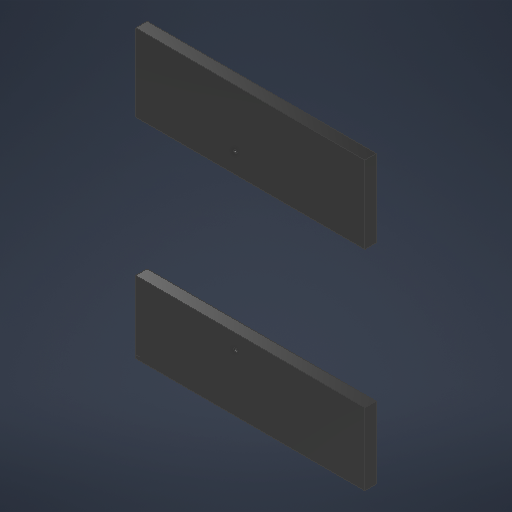
# Autodesk Inventor part: Part67
Saved by Autodesk Inventor 2027.1 (Build 311270010, 270A)
## iProperties
Created: 2026-10-12
Part Number: Part67
Material: Generic
Document SubType Name: Modeling
Designer: daniel
Density: 1 g/cm^3
Appearance: Default
Mass: 260.456 g
Surface Area: 629.456 cm^2
Volume: 260.456 cm^3
Author: daniel
Autodesk Inventor part; units mm, degrees
ref_plane "YZ Plane" through (0, 0, 0) normal (1, 0, 0) x (0, 1, 0)
ref_plane "XZ Plane" through (0, 0, 0) normal (0, 1, 0) x (-1, 0, 0)
ref_plane "XY Plane" through (0, 0, 0) normal (0, 0, 1) x (1, 0, 0)
sketch "Sketch1" plane through (0, 0, 0) normal (0, 0, 1) x (1, 0, 0)
  line L0 (100.0665, -125.0665) -> (100.0665, 124.9335)
  line L1 (100.0665, 124.9335) -> (100.0665, -125.0665)
  line L2 (-99.9335, 124.9335) -> (-99.9335, -125.0665)
  line L3 (100.0665, 37.4335) -> (100.0665, 57.4335)
  line L4 (97.0665, 57.4335) -> (97.0665, 77.3335)
  line L5 (97.0665, 77.3335) -> (100.0665, 77.3335)
  line L6 (97.0665, 77.3335) -> (100.0665, 77.3335)
  line L7 (100.0665, 77.3335) -> (100.0665, 57.4335)
  line L8 (97.0665, 97.3335) -> (97.0665, 77.3335)
  line L9 (100.0665, 121.9335) -> (100.0665, 124.9335)
  line L10 (100.0665, 57.4335) -> (97.0665, 57.4335)
  line L11 (100.0665, 57.4335) -> (97.0665, 57.4335)
  line L12 (57.0665, 121.9335) -> (37.1665, 121.9335)
  line L13 (100.0665, 77.3335) -> (100.0665, 97.3335)
  line L14 (97.0665, 57.4335) -> (97.0665, 37.4335)
  line L15 (-99.9335, -125.0665) -> (100.0665, -125.0665)
  line L16 (100.0665, 124.9335) -> (77.0665, 124.9335)
  line L17 (37.1665, 124.9335) -> (57.0665, 124.9335)
  line L18 (100.0665, 124.9335) -> (-99.9335, 124.9335)
  line L19 (77.0665, 121.9335) -> (100.0665, 121.9335)
  line L20 (77.0665, 121.9335) -> (57.0665, 121.9335)
  line L21 (77.0665, 124.9335) -> (77.0665, 121.9335)
  line L22 (77.0665, 124.9335) -> (77.0665, 121.9335)
  line L23 (37.1665, 121.9335) -> (37.1665, 124.9335)
  line L24 (37.1665, 124.9335) -> (37.1665, 121.9335)
  line L25 (37.1665, 121.9335) -> (17.1665, 121.9335)
  line L26 (17.1665, 124.9335) -> (37.1665, 124.9335)
  line L27 (57.0665, 124.9335) -> (57.0665, 121.9335)
  line L28 (57.0665, 121.9335) -> (57.0665, 124.9335)
  line L29 (-22.7335, 121.9335) -> (-22.7335, 124.9335)
  line L30 (-92.7335, 124.9335) -> (-72.7335, 124.9335)
  line L31 (-72.7335, 124.9335) -> (-99.9335, 124.9335)
  line L32 (-99.9335, 124.9335) -> (-99.9335, 121.9335)
  line L33 (-99.9335, 124.9335) -> (-96.9335, 124.9335)
  line L34 (-96.9335, 124.9335) -> (-96.9335, 97.3335)
  line L35 (-99.9335, 97.3335) -> (-99.9335, 124.9335)
  line L36 (-99.9335, 97.9335) -> (-99.9335, 121.9335)
  line L37 (-96.9335, 97.3335) -> (-99.9335, 97.3335)
  line L38 (-99.9335, 97.3335) -> (-96.9335, 97.3335)
  line L39 (-96.9335, 97.3335) -> (-96.9335, 77.3335)
  line L40 (-96.9335, 77.3335) -> (-99.9335, 77.3335)
  line L41 (-96.9335, 77.3335) -> (-99.9335, 77.3335)
  line L42 (-99.9335, 77.3335) -> (-99.9335, 97.3335)
  line L43 (-99.9335, 121.9335) -> (-96.9335, 121.9335)
  line L44 (17.1665, 121.9335) -> (17.1665, 124.9335)
  line L45 (17.1665, 121.9335) -> (-2.7335, 121.9335)
  line L46 (-2.7335, 121.9335) -> (-2.7335, 124.9335)
  line L47 (-2.7335, 124.9335) -> (17.1665, 124.9335)
  line L48 (17.1665, 124.9335) -> (17.1665, 121.9335)
  line L49 (-2.7335, 121.9335) -> (-22.7335, 121.9335)
  line L50 (-2.7335, 124.9335) -> (-2.7335, 121.9335)
  line L51 (-22.7335, 124.9335) -> (-2.7335, 124.9335)
  line L52 (-99.9335, 57.4335) -> (-96.9335, 57.4335)
  line L53 (-99.9335, 57.4335) -> (-96.9335, 57.4335)
  line L54 (-99.9335, 77.3335) -> (-99.9335, 57.4335)
  line L55 (-96.9335, 37.4335) -> (-99.9335, 37.4335)
  line L56 (-96.9335, 57.4335) -> (-96.9335, 37.4335)
  line L57 (-99.9335, 37.4335) -> (-99.9335, 57.4335)
  line L58 (-99.9335, 37.4335) -> (-96.9335, 37.4335)
  line L59 (-99.9335, 17.5335) -> (-99.9335, 37.4335)
  line L60 (-96.9335, 37.4335) -> (-96.9335, 17.5335)
  line L61 (-96.9335, 57.4335) -> (-96.9335, 77.3335)
  line L62 (-96.9335, 17.5335) -> (-99.9335, 17.5335)
  line L63 (-99.9335, 17.5335) -> (-96.9335, 17.5335)
  line L64 (-96.9335, -2.4665) -> (-99.9335, -2.4665)
  line L65 (-99.9335, -2.4665) -> (-96.9335, -2.4665)
  line L66 (-96.9335, 17.5335) -> (-96.9335, -2.4665)
  line L67 (-96.9335, -22.3665) -> (-99.9335, -22.3665)
  line L68 (-99.9335, -22.3665) -> (-96.9335, -22.3665)
  line L69 (-96.9335, -2.4665) -> (-96.9335, -22.3665)
  line L70 (-99.9335, -22.3665) -> (-99.9335, -2.4665)
  line L71 (-99.9335, -2.4665) -> (-99.9335, 17.5335)
  line L72 (-96.9335, -22.3665) -> (-96.9335, -42.3665)
  line L73 (-99.9335, -42.3665) -> (-99.9335, -22.3665)
  line L74 (-96.9335, -42.3665) -> (-99.9335, -42.3665)
  line L75 (-99.9335, -42.3665) -> (-96.9335, -42.3665)
  line L76 (-96.9335, -62.2665) -> (-99.9335, -62.2665)
  line L77 (-99.9335, -62.2665) -> (-99.9335, -42.3665)
  line L78 (-99.9335, -62.2665) -> (-96.9335, -62.2665)
  line L79 (-99.9335, -82.2665) -> (-99.9335, -62.2665)
  line L80 (-96.9335, -62.2665) -> (-96.9335, -82.2665)
  line L81 (-96.9335, -42.3665) -> (-96.9335, -62.2665)
  line L82 (-96.9335, -82.2665) -> (-99.9335, -82.2665)
  line L83 (-99.9335, -82.2665) -> (-96.9335, -82.2665)
  line L84 (-96.9335, -82.2665) -> (-96.9335, -102.1665)
  line L85 (-99.9335, -102.1665) -> (-99.9335, -82.2665)
  line L86 (-96.9335, -102.1665) -> (-99.9335, -102.1665)
  line L87 (-99.9335, -102.1665) -> (-96.9335, -102.1665)
  line L88 (-96.9335, -102.1665) -> (-96.9335, -122.1665)
  line L89 (-96.9335, -122.1665) -> (-99.9335, -122.1665)
  line L90 (-92.6335, -122.0665) -> (-99.9335, -122.0665)
  line L91 (-99.9335, -125.0665) -> (-42.6335, -125.0665)
  line L92 (-99.9335, -122.0665) -> (-99.9335, -125.0665)
  line L93 (-99.9335, -122.1665) -> (-99.9335, -102.1665)
  line L94 (97.0665, 97.3335) -> (100.0665, 97.3335)
  line L95 (100.0665, 97.3335) -> (97.0665, 97.3335)
  line L96 (100.0665, 121.9335) -> (97.0665, 121.9335)
  line L97 (100.0665, 97.9335) -> (100.0665, 121.9335)
  line L98 (100.0665, 124.9335) -> (100.0665, 121.9335)
  line L99 (100.0665, 124.9335) -> (97.0665, 124.9335)
  line L100 (100.0665, 97.3335) -> (100.0665, 124.9335)
  line L101 (97.0665, 124.9335) -> (97.0665, 97.3335)
  line L102 (57.0665, 124.9335) -> (77.0665, 124.9335)
  line L103 (97.0665, 37.4335) -> (100.0665, 37.4335)
  line L104 (100.0665, 37.4335) -> (97.0665, 37.4335)
  line L105 (97.0665, 37.4335) -> (97.0665, 17.5335)
  line L106 (100.0665, 17.5335) -> (100.0665, 37.4335)
  line L107 (100.0665, 17.5335) -> (97.0665, 17.5335)
  line L108 (97.0665, 17.5335) -> (100.0665, 17.5335)
  line L109 (100.0665, -2.4665) -> (100.0665, 17.5335)
  line L110 (97.0665, -2.4665) -> (100.0665, -2.4665)
  line L111 (100.0665, -2.4665) -> (97.0665, -2.4665)
  line L112 (97.0665, 17.5335) -> (97.0665, -2.4665)
  line L113 (100.0665, -22.3665) -> (100.0665, -2.4665)
  line L114 (97.0665, -2.4665) -> (97.0665, -22.3665)
  line L115 (100.0665, -22.3665) -> (97.0665, -22.3665)
  line L116 (97.0665, -22.3665) -> (100.0665, -22.3665)
  line L117 (100.0665, -42.3665) -> (100.0665, -22.3665)
  line L118 (97.0665, -22.3665) -> (97.0665, -42.3665)
  line L119 (100.0665, -42.3665) -> (97.0665, -42.3665)
  line L120 (97.0665, -42.3665) -> (97.0665, -62.2665)
  line L121 (100.0665, -62.2665) -> (100.0665, -42.3665)
  line L122 (97.0665, -42.3665) -> (100.0665, -42.3665)
  line L123 (97.0665, -62.2665) -> (100.0665, -62.2665)
  line L124 (100.0665, -62.2665) -> (97.0665, -62.2665)
  line L125 (97.0665, -62.2665) -> (97.0665, -82.2665)
  line L126 (100.0665, -82.2665) -> (100.0665, -62.2665)
  line L127 (97.0665, -82.2665) -> (100.0665, -82.2665)
  line L128 (100.0665, -82.2665) -> (97.0665, -82.2665)
  line L129 (97.0665, -82.2665) -> (97.0665, -102.1665)
  line L130 (100.0665, -102.1665) -> (100.0665, -82.2665)
  line L131 (97.0665, -102.1665) -> (100.0665, -102.1665)
  line L132 (100.0665, -102.1665) -> (97.0665, -102.1665)
  line L133 (97.0665, -102.1665) -> (97.0665, -122.1665)
  line L134 (100.0665, -122.1665) -> (100.0665, -102.1665)
  line L135 (97.0665, -122.1665) -> (100.0665, -122.1665)
  line L136 (100.0665, -122.0665) -> (100.0665, -125.0665)
  line L137 (77.0665, -122.0665) -> (100.0665, -122.0665)
  line L138 (100.0665, -125.0665) -> (77.0665, -125.0665)
  line L139 (77.0665, -125.0665) -> (77.0665, -122.0665)
  line L140 (77.0665, -122.0665) -> (77.0665, -125.0665)
  line L141 (57.0665, -125.0665) -> (57.0665, -122.0665)
  line L142 (57.0665, -122.0665) -> (57.0665, -125.0665)
  line L143 (77.0665, -125.0665) -> (57.0665, -125.0665)
  line L144 (57.0665, -122.0665) -> (77.0665, -122.0665)
  line L145 (57.0665, -125.0665) -> (37.1665, -125.0665)
  line L146 (37.1665, -122.0665) -> (57.0665, -122.0665)
  line L147 (37.1665, -125.0665) -> (37.1665, -122.0665)
  line L148 (37.1665, -122.0665) -> (37.1665, -125.0665)
  line L149 (37.1665, -125.0665) -> (17.1665, -125.0665)
  line L150 (17.1665, -122.0665) -> (37.1665, -122.0665)
  line L151 (17.1665, -125.0665) -> (17.1665, -122.0665)
  line L152 (17.1665, -125.0665) -> (17.1665, -122.0665)
  line L153 (-2.7335, -125.0665) -> (17.1665, -125.0665)
  line L154 (17.1665, -122.0665) -> (-2.7335, -122.0665)
  line L155 (-22.7335, -122.0665) -> (-92.6335, -122.0665)
  line L156 (-22.7335, -125.0665) -> (-22.7335, -122.0665)
  line L157 (-22.7335, -125.0665) -> (-22.7335, -122.0665)
  line L158 (-42.6335, -125.0665) -> (-22.7335, -125.0665)
  line L159 (-22.7335, -122.0665) -> (-2.7335, -122.0665)
  line L160 (-2.7335, -122.0665) -> (-2.7335, -125.0665)
  line L161 (-2.7335, -122.0665) -> (-2.7335, -125.0665)
  line L162 (-2.7335, -125.0665) -> (-22.7335, -125.0665)
  line L163 (-42.6335, -125.0665) -> (-62.6335, -125.0665)
  line L164 (-62.6335, -125.0665) -> (-62.6335, -122.0665)
  line L165 (-62.6335, -122.0665) -> (-42.6335, -122.0665)
  line L166 (-42.6335, -122.0665) -> (-42.6335, -125.0665)
  line L167 (-62.6335, -122.0665) -> (-82.5335, -122.0665)
  line L168 (-82.5335, -122.0665) -> (-82.5335, -125.0665)
  line L169 (-82.5335, -125.0665) -> (-62.6335, -125.0665)
  line L170 (-62.6335, -125.0665) -> (-62.6335, -122.0665)
  line L171 (-22.7335, 121.9335) -> (-42.6335, 121.9335)
  line L172 (-42.6335, 121.9335) -> (-42.6335, 124.9335)
  line L173 (-42.6335, 124.9335) -> (-22.7335, 124.9335)
  line L174 (-22.7335, 124.9335) -> (-22.7335, 121.9335)
  line L175 (-42.6335, 121.9335) -> (-62.6335, 121.9335)
  line L176 (-62.6335, 121.9335) -> (-62.6335, 124.9335)
  line L177 (-62.6335, 124.9335) -> (-42.6335, 124.9335)
  line L178 (-42.6335, 124.9335) -> (-42.6335, 121.9335)
  line L179 (-62.6335, 121.9335) -> (-82.5335, 121.9335)
  line L180 (-82.5335, 121.9335) -> (-82.5335, 124.9335)
  line L181 (-82.5335, 124.9335) -> (-62.6335, 124.9335)
  line L182 (-62.6335, 124.9335) -> (-62.6335, 121.9335)
  line L183 (-82.5335, 121.9335) -> (-99.9335, 121.9335)
  line L184 (-99.9335, 121.9335) -> (-99.9335, 124.9335)
  line L185 (-99.9335, 124.9335) -> (-82.5335, 124.9335)
  line L186 (-82.5335, 124.9335) -> (-82.5335, 121.9335)
  line L187 (-22.4335, -9.9665) -> (22.5665, -9.9665)
  line L188 (22.5665, -9.9665) -> (22.5665, 9.8335)
  line L189 (22.5665, 9.8335) -> (-22.4335, 9.8335)
  line L190 (-22.4335, 9.8335) -> (-22.4335, -9.9665)
  circle A0 centre (-12.8335, -0.0665) radius 75
  line L191 (-12.8335, -0.0665) -> (74.8331, -0.0665)
  line L192 (74.8331, -0.0665) -> (-100.6534, -0.0665)
  line L193 (-12.8335, -0.0665) -> (88.622, -0.0665) construction
  circle A1 centre (62.1665, -0.0665) radius 1.5
  circle A2 centre (-87.8335, -0.0665) radius 1.5
  line L194 (22.5665, -9.9665) -> (-22.4335, -9.9665)
  line L195 (-22.4335, 9.8335) -> (22.5665, 9.8335)
  line L196 (22.5665, -9.9665) -> (-22.4335, -9.9665)
  line L197 (-22.4335, -9.9665) -> (-22.4335, 9.8335)
  line L198 (-22.4335, 9.8335) -> (22.5665, 9.8335)
  line L199 (22.5665, 9.8335) -> (22.5665, -9.9665)
  line L200 (-22.4335, -9.9665) -> (-22.4335, 9.8335)
  circle A3 centre (-12.8335, -0.0665) radius 1.6
  line L201 (-29.4335, 16.8335) -> (29.5665, 16.8335)
  line L202 (29.5665, 16.8335) -> (29.5665, -16.9665)
  line L203 (29.5665, -16.9665) -> (-29.4335, -16.9665)
  line L204 (-29.4335, -16.9665) -> (-29.4335, 16.8335)
  line L205 (97.0665, 57.4335) -> (-96.9335, 57.4335)
  line L206 (-96.9335, 57.4335) -> (-96.9335, -62.2665)
  line L207 (-96.9335, -62.2665) -> (97.0665, -62.2665)
  line L208 (97.0665, -62.2665) -> (97.0665, 57.4335)
  line L209 (-12.8335, -0.0665) -> (-92.6335, -0.0665)
  line L210 (-92.6335, -0.0665) -> (50.6957, -0.0665)
  line L211 (-12.8335, -84.1887) -> (-12.8335, 81.3877)
  circle A4 centre (-12.8335, -75.0665) radius 1.5
  circle A5 centre (-12.8335, 74.9335) radius 1.5
  point P0 (0, 0)
  point P1 (18.4571, -44.9101)
  point P2 (92.8665, 124.9335)
  point P3 (-99.9335, -0.0665)
  point P4 (-22.4335, -0.0665)
  point P5 (-12.7335, -125.0665)
  point P6 (24.069, -37.7336)
  point P7 (-96.9335, -122.0665)
  point P8 (97.0665, -122.0665)
  point P9 (-96.9335, 57.4335)
  dimension "d0" = 200
  dimension "d1" = 250
  dimension "d2" = 23
  dimension "d3" = 3
  dimension "d4" = 20
  dimension "d5" = 19.9
  dimension "d6" = 20
  dimension "d7" = 19.9
  dimension "d8" = 20
  dimension "d9" = 3
  dimension "d10" = 27.6
  dimension "d11" = 3
  dimension "d12" = 20
  dimension "d13" = 19.9
  dimension "d14" = 20
  dimension "d15" = 19.9
  dimension "d16" = 20
  dimension "d17" = 19.9
  dimension "d18" = 20
  dimension "d19" = 19.9
  dimension "d20" = 20
  dimension "d21" = 3
  dimension "d22" = 19.9
  dimension "d23" = 20
  dimension "d24" = 23
  dimension "d25" = 3
  dimension "d26" = 20
  dimension "d27" = 19.9
  dimension "d28" = 19.9
  dimension "d29" = 19.9
  dimension "d30" = 20
  dimension "d31" = 19.9
  dimension "d32" = 19.9
  dimension "d33" = 20
  dimension "d34" = 19.9
  dimension "d35" = 45
  dimension "d36" = 19.8
  dimension "d37" = 77.5
  dimension "d38" = 115.1
  dimension "d39" = 9.8335
  dimension "d40" = 22.5665
  dimension "d41" = 150
  dimension "d43" = 3
  dimension "d44" = 3
  dimension "d47" = 9.9
  dimension "d48" = 9.6
  dimension "d49" = 3.2
  dimension "d50" = 0
  dimension "d52" = 45
  dimension "d53" = 0
  dimension "d54" = 7
  dimension "d57" = 0
  dimension "d58" = 3
  dimension "d59" = 3
  constraints: 422 end point, 72 parallel, 39 horizontal, 37 perpendicular, 34 point on line, 6 centre point, 4 point on circle, 3 midpoint, 1 coincident, 1 vertical, 14 other
  measures "d0" distance of L0.start L2.end
  measures "d1" distance of L2.end L2.start
  measures "d2" distance of L19.end L19.start
  measures "d3" distance of L19.start L22.start
  measures "d4" distance of L102.start L21.start
  measures "d5" distance of L17.start L27.start
  measures "d6" distance of L44.end L26.end
  measures "d7" distance of L47.start L47.end
  measures "d8" distance of L51.start L50.start
  measures "d9" distance of L34.end L37.end
  measures "d10" distance of L33.end L34.end
  measures "d11" distance of L39.end L42.start
  measures "d12" distance of L38.end L39.end
  measures "d13" distance of L57.end L41.end
  measures "d14" distance of L56.start L55.start
  measures "d15" distance of L58.end L62.start
  measures "d16" distance of L66.start L66.end
  measures "d17" distance of L65.end L69.end
  measures "d18" distance of L68.end L74.start
  measures "d19" distance of L75.end L76.start
  measures "d20" distance of L78.end L80.end
  measures "d21" distance of L86.start L86.end
  measures "d22" distance of L83.end L86.start
  measures "d23" distance of L87.end L88.end
  measures "d24" distance of L137.start L136.start
  measures "d25" distance of L143.start L137.start
  measures "d26" distance of L141.end L144.end
  measures "d27" distance of L147.end L142.start
  measures "d28" distance of L152.start L160.end
  measures "d29" distance of L158.end L158.start
  measures "d30" distance of L167.start L165.end
  measures "d31" distance of L170.start L168.end
  measures "d32" distance of L172.end L173.end
  measures "d33" distance of L176.end L178.start
  measures "d34" distance of L181.start L181.end
  measures "d35" distance of L190.start L189.start
  measures "d36" distance of L189.start L188.start
  measures "d37" distance of point (-99.933, -0.067) point (-22.433, -0.067)
  measures "d38" distance from line of point (-12.733, -125.067) L187
  measures "d39" distance from line of L189 point (0, 0)
  measures "d40" distance from line of L188 point (0, 0)
  measures "d41" diameter of A0
  measures "d43" diameter of A1
  measures "d44" diameter of A2
  measures "d47" distance from line of L195 L191.start
  measures "d48" distance from line of L200 L191.start
  measures "d49" diameter of A3
  measures "d50" distance between parallel lines of L189 L198
  measures "d52" distance between parallel lines of L197 L199
  measures "d53" distance between parallel lines of L188 L199
  measures "d54" distance between parallel lines of L189 L201
  measures "d57" distance between parallel lines of L210 L192
  measures "d58" diameter of A4
  measures "d59" diameter of A5
extrude "Extrusion1" add sketch "Sketch1" along normal blind 10 contours L15 L139 L137 L133 L135 L0 | L135 L133 L137 L0 | L15 L141 L144 L139 | L137 L133 L131 L0 | L15 L147 L146 L141 | L144 L146 L150 L154 L159 L155 L90 L88 L84 L80 L207 A0 A4 L125 L129 L133 L137 | L131 L129 L127 L0 | L15 L151 L150 L147 | L127 L125 L123 L0 | L15 L160 L154 L151 | L15 L156 L159 L160 | L15 L166 L155 L156 | A0 A4 L211 L207 | L15 L164 L155 L166 | L211 A4 A0 L207 | L15 L168 L155 L164 | L15 L2 L89 L88 L90 L155 L168 | L80 L82 L2 L76 | L10 L4 L5 L0 | L205 L211 A5 A0 | A0 A5 L205 L61 L39 L34 L183 L179 L175 L171 L49 L45 L25 L12 L20 L19 L101 L8 L4 | L84 L86 L2 L82 | L5 L8 L94 L0 | L205 A0 A5 L211 | L88 L90 L2 L86 | L94 L101 L19 L0 | L52 L2 L40 L61 | L19 L101 L16 L0 | L19 L21 L16 L101 | L40 L2 L37 L39 | L20 L27 L18 L21 | L37 L2 L43 L34 | L12 L23 L17 L27 | L43 L2 L18 L34 | L34 L18 L180 L183 | L25 L44 L18 L23 | L180 L18 L176 L179 | L45 L46 L18 L44 | L176 L18 L172 L175 | L49 L29 L18 L46 | L172 L18 L29 L171
equation "\"d37\" = -0.5 * d35 + 0.5 * d0"
equation "\"d38\" = -0.5 * d36 + 0.5 * d1"
equation "\"d43\" = d58"
equation "\"d44\" = d58"
equation "\"d59\" = d58"
body "Solid1"
